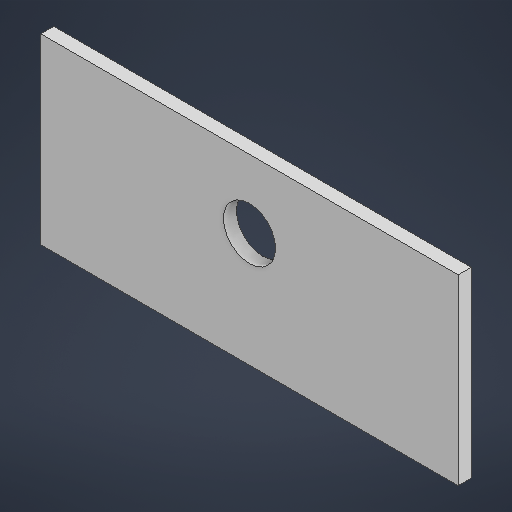
# Autodesk Inventor part: wheel support
Saved by Autodesk Inventor 2025.2 (Build 292293000, 293)
## iProperties
Created: 2024-12-25
Part Number: wheel support
Material: Generic
Document SubType Name: Modeling
Designer: user
Density: 1 g/cm^3
Appearance: Default
Author: user
Autodesk Inventor part; units mm, degrees
ref_plane "YZ Plane" through (0, 0, 0) normal (1, 0, 0) x (0, 1, 0)
ref_plane "XZ Plane" through (0, 0, 0) normal (0, 1, 0) x (-1, 0, 0)
ref_plane "XY Plane" through (0, 0, 0) normal (0, 0, 1) x (1, 0, 0)
sketch "Sketch1" plane through (0, 0, 0) normal (0, 0, 1) x (1, 0, 0)
  line L0 (-12.9786, 64.4466) -> (147.0214, 64.4466)
  line L1 (147.0214, 64.4466) -> (147.0214, -5.5534)
  line L2 (147.0214, -5.5534) -> (-12.9786, -5.5534)
  line L3 (-12.9786, -5.5534) -> (-12.9786, 64.4466)
  point P0 (0, 0)
  dimension "d0" = 160
  dimension "d1" = 70
  constraints: 8 end point, 2 parallel, 1 horizontal, 1 perpendicular
  measures "d0" distance of L1.end L2.end
  measures "d1" distance of L0.end L1.end
extrude "Extrusion1" add sketch "Sketch1" along normal blind 5
sketch "Sketch2" plane through (0, 0, 5) normal (0, 0, 1) x (1, 0, 0)
  circle A0 centre (67.0214, 38.1766) radius 10
  line L0 (-12.9786, -5.5534) -> (147.0214, -5.5534) projected
  point P0 (0, 0)
  dimension "d4" = 20
  dimension "d5" = 43.73
  constraints: 1 centre point
  measures "d4" diameter of A0
  measures "d5" distance from line of L0 A0.centre
extrude "Extrusion2" cut sketch "Sketch2" against normal blind 5
body "Solid1"
